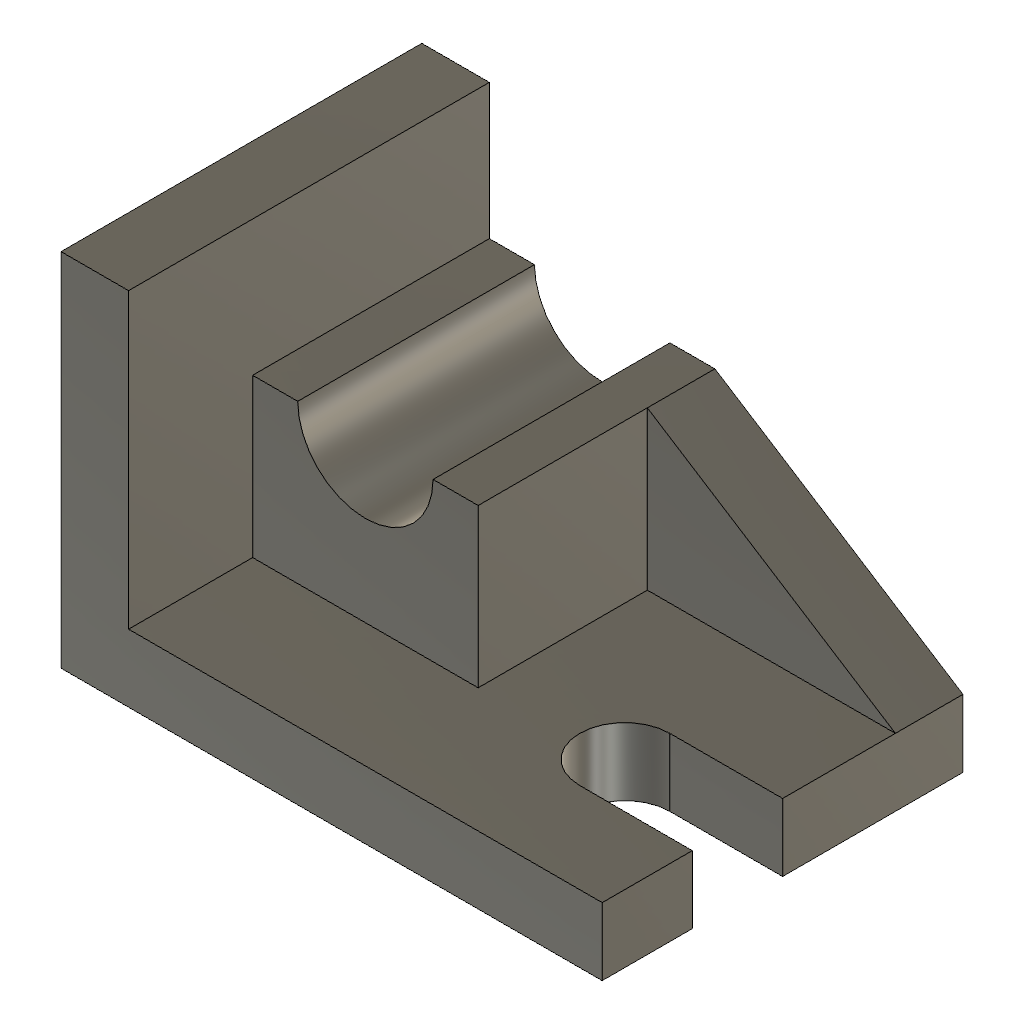
3D_2 (Autodesk Fusion 360 design; units mm, degrees)
part number: 2026-09-30-14-53-26-012
Autodesk Fusion 360 part; units mm, degrees
sketch "Sketch1" plane through (0, 0, 0) normal (0, 0, 1) x (1, 0, 0)
  line L0 (48, -32) -> (-48, -32)
  line L1 (-48, -32) -> (-48, 32)
  line L2 (-48, 32) -> (48, 32)
  line L3 (48, 32) -> (48, -32)
  line L4 (48, -32) -> (-48, 32) construction
  line L5 (-48, -32) -> (48, 32) construction
  line L6 (48, -16) -> (28, -16)
  line L7 (28, -16) -> (28, 0)
  line L8 (28, 0) -> (48, 0)
  line L9 (48, 0) -> (48, -16)
  circle A0 centre (28, -8) radius 8
  dimension "d1" = 96
  dimension "d2" = 64
  dimension "d3" = 16
  dimension "d4" = 16
  dimension "d5" = 16
  dimension "d6" = 20
  constraint horizontal L0
  constraint perpendicular L0 L1
  constraint parallel L0 L2
  constraint parallel L1 L3
  constraint coincident L4 origin
  constraint coincident L5 origin
  constraint horizontal L6
  constraint vertical L7
  constraint horizontal L8
  constraint vertical L9
  constraint coincident L3 L6.start
  constraint midpoint L7 A0.centre
  measures "d1" distance of L1.end L2.end
  measures "d2" distance of L0.end L1.end
  measures "d3" distance of L0 L6
  measures "d4" distance of L6 L8
  measures "d5" diameter of A0
  measures "d6" distance of L7.end L8.end
extrude "Extrude1" add sketch "Sketch1" along normal blind 12 contours L0 L1 L2 L3 L6 L8 A0
sketch "Sketch2" plane through (0, 0, 12) normal (0, 0, 1) x (-1, 0, 0)
  line L0 (-48, 16) -> (-28, 16)
  arc A0 (-28, 0) -> (-28, 16) centre (-28, 8) ccw
  line L1 (-28, 0) -> (-48, 0)
  line L2 (-48, 0) -> (-48, -32)
  line L3 (-48, -32) -> (48, -32)
  line L4 (48, -32) -> (48, 32)
  line L5 (48, 32) -> (-48, 32)
  line L6 (-48, 32) -> (-48, 16)
  line L7 (48, -32) -> (36, -32)
  line L8 (36, -32) -> (36, 32)
  line L9 (36, 32) -> (48, 32)
  line L10 (48, 32) -> (48, -32)
  line L11 (36, -32) -> (-4, -32)
  line L12 (-4, -32) -> (-4, 10)
  line L13 (-4, 10) -> (36, 10)
  line L14 (36, 10) -> (36, -32)
  dimension "d9" = 12
  dimension "d10" = 40
  dimension "d11" = 22
  constraint horizontal L7
  constraint vertical L8
  constraint horizontal L9
  constraint vertical L10
  constraint coincident L3.end L4.start
  constraint horizontal L11
  constraint vertical L12
  constraint horizontal L13
  constraint vertical L14
  measures "d9" distance of L3.end L7.end
  measures "d10" distance of L7.end L11.end
  measures "d11" distance of L5 L13
extrude "Extrude2" add sketch "Sketch2" along normal blind 52 contours L3 L4 L5 L7 L8 L9 L10 L14
extrude "Extrude3" add sketch "Sketch2" along normal blind 28 contours L3 L8 L11 L12 L13 L14
sketch "Sketch3" plane through (0, 32, 0) normal (0, 1, 0) x (-1, 0, 0)
  line L0 (-48, 0) -> (48, 0)
  line L1 (48, 0) -> (48, 64)
  line L2 (48, 64) -> (36, 64)
  line L3 (36, 64) -> (36, 40)
  line L4 (36, 40) -> (-4, 40)
  line L5 (-4, 40) -> (-4, 12)
  line L6 (-4, 12) -> (-48, 12)
  line L7 (-48, 12) -> (-48, 0)
  circle A0 centre (16, 40) radius 12
  line L8 (-4, 40) -> (-48, 12)
  dimension "d16" = 24
  constraint midpoint L4 A0.centre
  constraint coincident L4.end L5.start
  constraint coincident L6.end L7.start
  measures "d16" diameter of A0
extrude "Extrude4" cut sketch "Sketch3" against normal blind 60 contours L4 A0 picked at (16.2989, 32.5401)
extrude "Extrude5" add sketch "Sketch3" against normal blind 12 contours L5 L6 L8
equation "d10 = 8 mm + 24 mm + 8 mm"
equation "d12 = 64 mm - 12 mm"
